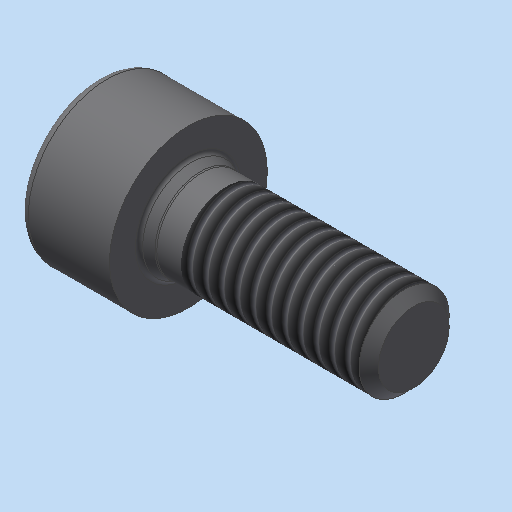
# Autodesk Inventor part: Zylinderschraube_ISO_4762___M4x10
Saved by Autodesk Inventor 2023.3 (Build 273359000, 359)
## iProperties
Shininess: 64.0
Length Units: 11269
Angle Units: 11279
Time Units: 11290
Mass Units: 11283
Length Display Precision: 3
Angle Display Precision: 2
Compacted: True
Part Number: Zylinderschraube_ISO_4762___M4x10
Document SubType Name: Modeling
Created: 2004-04-03
Material: xStahl_AnP_Dummymaterial
Description: =<RBPARTNOTITLE2>
Vendor: NORM8
Designer: S.Riedelsheimer
Manufacturer: Standard
Standards Organization: Custom
Density: 7.85 g/cm^3
Appearance: Stahl - normal AnP
DOC_ID: 5 F45 Zylinderschraube_ISO_4762___M4x10
GAIN_REFID: 20__Zylinderschraube_ISO_4762___M4x10:A95AC
Control State: 0
Master: False
Checked Out: False
CNS_NB: Zylinderschraube ISO 4762 - M4x10
CNS_NN: ISO 4762
CNS_NT: Zylinderschrauben mit Innensechskant
CNS_NBSYN: Zylinderschraube ISO 4762 - $NENN.
CNS_LINA: Zylinderschraube ISO 4762 - M4x10
CNS_D: 4.000
CNS_D3: 3.141
CNS_P: 0.700
CNS_L: 10.000
CNS_S: 3.000
CNS_HM: 10.000
CNS_DK: 7.000
CNS_DA: 4.700
CNS_DS: 4.000
CNS_E: 3.440
CNS_K: 4.000
CNS_R: 0.200
CNS_T: 2.000
CNS_V: 0.400
CNS_DW: 6.530
CNS_W: 1.400
CNS_LF: 0.600
CNS_LG: 2.100
CNS_FORM: 1.000
CNS_NENN: M4x10
CNS_KT: DUMMY
PSOL_IDENT_0: {C:\partsolutions8\data\23d-libs\bosch_bamberg\schrauben\zylinderschrauben\din_en_iso_4762.prj},170
PSOL_IDENT_1: {M=Nenngewinde},{VTYP=3D},{NB=Zylinderschraube ISO 4762 - M4x10},{NN=ISO 4762},{DATE=26.11.2003},{GE
PSOL_IDENT_2: OMDATE=26.11.2003},{VERSION=v2},{LINEID=390},{LINESUBID=-1},{WBVAR=}  {NB=Zylinderschraube ISO 4762
PSOL_IDENT_3: - M4x10},{LINA=Zylinderschraube ISO 4762 - M4x10},{KT=DUMMY},{IDNR=},{D=4.000},{D3=3.141},{P=0.700},
PSOL_IDENT_4: {L=10.000},{S=3.000},{HM=10.000},{DK=7.000},{DA=4.700},{DS=4.000},{E=3.440},{K=4.000},{R=0.200},{T=2
PSOL_IDENT_5: .000},{V=0.400},{DW=6.530},{W=1.400},{LF=0.600},{LG=2.100},{FORM=1.000},{NENN=M4x10}
DEF_STKID: T18526
Bezeichnung1: Zylinderschraube ISO 4762 - M4x10
Bezeichnung2: Zylinderschrauben mit Innensechskant
RBPARTNOTITLE2: Zylinderschrauben mit Innensechskant
RBPARTNOTITLE1: Hexagon socket head cap screws
AnP_Kategorie: 4
RBDRAWINGMISSINGSPEC: --
RBPARTMADEOF: ISO 4762 - M4x10 - 8.8 verzinkt
Density: 0.0
Volumn: 0.0
Area: 0.0
PropertySet Name: Model Information
Title: Zylinderschraube ISO 4762 - M4x10
Author: S.Riedelsheimer
Keywords: =<RBPARTMADEOF>
Comments: =<RBSURFACE2>
Revision Number: 01
Autodesk Inventor part; units mm, degrees
sketch "Skizze_2" plane through (0, 0, 0) normal (0, 0, 1) x (1, 0, 0)
  line L0 (13, 0) -> (-7, 0)
  line L1 (-0.534, 0) -> (-1.4, 1.5)
  line L2 (-1.4, 1.5) -> (-3.78, 1.5)
  line L3 (-3.78, 1.5) -> (-4, 1.72)
  line L4 (-4, 1.72) -> (-4, 3.1)
  arc A0 (-3.6, 3.5) -> (-4, 3.1) centre (-3.6, 3.1) ccw
  line L5 (-3.6, 3.5) -> (0, 3.5)
  line L6 (0, 3.5) -> (0, 2.35)
  arc A1 (0, 2.35) -> (0.1298, 2.1627) centre (0.2, 2.35) ccw
  line L7 (0.1298, 2.1627) -> (0.5298, 2.0127)
  arc A2 (0.5298, 2.0127) -> (0.6, 2) centre (0.6, 2.2) ccw
  line L8 (0.6, 2) -> (9.5705, 2)
  line L9 (9.5705, 2) -> (10, 1.5705)
  line L10 (10, 1.5705) -> (10, 0)
  line L11 (10, 0) -> (-0.534, 0)
  constraints: 24 end point, 6 point on circle, 3 centre point
revolve "Drehung1" add sketch "Skizze_2" angle 360 about axis through (13, 0, 0) along (1, 0, 0)
thread "Gewinde1" size "M4x0.7" class "6g" standard "ANSI Metric M Profile" length 7.9
sketch "Skizze_1" plane through (-1.4, 0, 0) normal (1, 0, 0) x (0, 0, -1)
  line L0 (-1.5, 0.866) -> (-1.5, -0.866)
  line L1 (-1.5, -0.866) -> (0, -1.7321)
  line L2 (0, -1.7321) -> (1.5, -0.866)
  line L3 (1.5, -0.866) -> (1.5, 0.866)
  line L4 (1.5, 0.866) -> (0, 1.7321)
  line L5 (0, 1.7321) -> (-1.5, 0.866)
  constraints: 12 end point
extrude "Extrusion1" cut sketch "Skizze_1" against normal blind 4
ref_plane "IP1_XY" through (0, 0, 0) normal (1, 0, 0) x (0, 0, -1)
ref_plane "IP1_YZ" through (0, 0, 0) normal (0, 0, -1) x (0, 1, 0)
ref_plane "IP3_XY" through (10, 0, 0) normal (1, 0, 0) x (0, 0, -1)
ref_plane "IP3_YZ" through (10, 0, 0) normal (0, 0, -1) x (0, 1, 0)
ref_plane "IP2_XY" through (-4, 0, 0) normal (1, 0, 0) x (0, 0, -1)
ref_plane "IP2_YZ" through (-4, 0, 0) normal (0, 0, -1) x (0, 1, 0)
